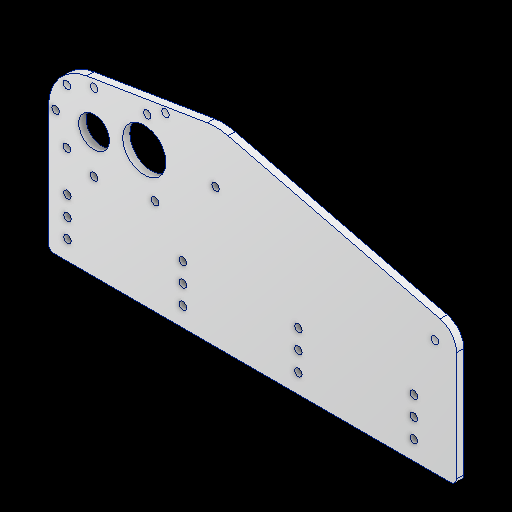
# Autodesk Inventor part: INTK_003_bar holder thingy
Saved by Autodesk Inventor 2027.1 (Build 311270010, 270A)
## iProperties
Created: 2026-11-21
Part Number: INTK_003_bar holder thingy
Material: Aluminum 6061
Document SubType Name: Modeling
Designer: Stanley Ruangsuwan
Density: 2.7 g/cm^3
Appearance: Aluminum - Flat
Author: Stanley Ruangsuwan
Autodesk Inventor part; units mm, degrees
ref_plane "YZ Plane" through (0, 0, 0) normal (1, 0, 0) x (0, 1, 0)
ref_plane "XZ Plane" through (0, 0, 0) normal (0, 1, 0) x (-1, 0, 0)
ref_plane "XY Plane" through (0, 0, 0) normal (0, 0, 1) x (1, 0, 0)
sketch "Sketch1" plane through (0, 0, 0) normal (0, 0, 1) x (1, 0, 0)
  circle A0 centre (-159.0509, 91.44) radius 34.29
  circle A1 centre (-14.2875, 76.2) radius 14.2875
  circle A2 centre (-159.0509, 91.44) radius 2.4892
  circle A3 centre (-14.2875, 76.2) radius 2.4892
  line L0 (-150.8089, 124.7247) -> (-10.8533, 90.0686)
  line L1 (0, 76.2) -> (0, 50.8)
  line L2 (-269.5173, 50.8) -> (0, 50.8)
  line L3 (0, 50.8) -> (-269.5173, 50.8)
  line L4 (-269.5173, 50.8) -> (-269.5173, 0)
  line L5 (-269.5173, 0) -> (0, 0)
  line L6 (0, 0) -> (0, 50.8)
  circle A4 centre (-256.8173, 38.1) radius 2.4892
  circle A5 centre (-256.8173, 25.4) radius 2.4892
  circle A6 centre (-256.8173, 12.7) radius 2.4892
  circle A7 centre (-180.6173, 38.1) radius 2.4892
  circle A8 centre (-180.6173, 25.4) radius 2.4892
  circle A9 centre (-180.6173, 12.7) radius 2.4892
  circle A10 centre (-104.4173, 38.1) radius 2.4892
  circle A11 centre (-104.4173, 25.4) radius 2.4892
  circle A12 centre (-104.4173, 12.7) radius 2.4892
  circle A13 centre (-28.2173, 38.1) radius 2.4892
  circle A14 centre (-28.2173, 25.4) radius 2.4892
  circle A15 centre (-28.2173, 12.7) radius 2.4892
  circle A16 centre (-239.2133, 82.6403) radius 30.0609
  circle A17 centre (-239.2133, 108.0403) radius 2.4892
  circle A18 centre (-206.1171, 88.9) radius 12.7 construction
  circle A19 centre (-239.2133, 82.6403) radius 10.16
  circle A20 centre (-257.1738, 100.6008) radius 2.4892
  circle A21 centre (-264.6133, 82.6403) radius 2.4892
  circle A22 centre (-257.1738, 64.6798) radius 2.4892
  circle A23 centre (-206.1171, 88.9) radius 14.2875
  line L7 (-164.5749, 125.2821) -> (-244.056, 112.3085)
  line L8 (-269.2734, 82.869) -> (-269.5173, 50.8)
  circle A24 centre (-204.1552, 110.3165) radius 6.35 construction
  line L9 (-209.1393, 106.3819) -> (-215.6186, 101.2668)
  line L10 (-198.2975, 107.865) -> (-190.6825, 104.6781)
  circle A25 centre (-198.9862, 63.2284) radius 6.35 construction
  line L11 (-204.7052, 65.9881) -> (-212.1398, 69.5757)
  line L12 (-193.7998, 66.8922) -> (-187.0575, 71.6552)
  circle A26 centre (-204.1552, 110.3165) radius 2.4892
  circle A27 centre (-198.9862, 63.2284) radius 2.4892
  circle A28 centre (-239.2133, 57.2403) radius 2.4892
  circle A29 centre (-192.0809, 117.0349) radius 6.35 construction
  circle A30 centre (-192.0809, 117.0349) radius 2.4892
  dimension "d0" = 68.58
  dimension "d1" = 28.575
  dimension "d5" = 4.9784
  dimension "d7" = 50.8
  dimension "d8" = 12.7
  dimension "d11" = 12.7
  dimension "d14" = 76.2
  dimension "d17" = 139.9556
  dimension "d19" = 25.4
  dimension "d20" = 12.7
  dimension "d21" = 40.64
  dimension "d22" = 4.9784
  dimension "d25" = 60.1218
  dimension "d27" = 25.4
  dimension "d32" = 47.0662
  dimension "d33" = 25.4
  dimension "d34" = 269.5174
  dimension "d35" = 20.32
  dimension "d38" = 180
  dimension "d40" = 28.575
  dimension "d41" = 33.0962
  dimension "d42" = 31.8403
  dimension "d43" = 38.1
  dimension "d44" = 12.7
  dimension "d45" = 8.255
  dimension "d56" = 80.1624
  dimension "d57" = 80.6439
  dimension "d59" = 33.683
  dimension "d60" = 12.7
  dimension "d61" = 13.8176
  dimension "d62" = 3.7084
  dimension "d63" = 4.9784
  constraints: 31 centre point, 26 end point, 14 point on circle, 9 coincident, 8 point on line, 6 tangent, 5 equal radius, 3 equal length, 3 horizontal, 2 parallel, 2 vertical, 1 perpendicular, 1 vertical alignment, 31 other
  measures "d0" diameter of A0
  measures "d1" diameter of A1
  measures "d5" diameter of A2
  measures "d7" distance of L3.end L4.end
  measures "d8" distance from line of L2 A4.centre
  measures "d11" distance of A4.centre A5.centre
  measures "d14" distance of A4.centre A7.centre
  measures "d17" horizontal distance of L0.start L0.end
  measures "d19" distance of L1.start L1.end
  measures "d20" distance from line of L4 A4.centre
  measures "d21" distance from line of L3 A0.centre
  measures "d22" diameter of A4
  measures "d25" diameter of A16
  measures "d27" distance of A16.centre A17.centre
  measures "d32" horizontal distance of A0.centre A18.centre
  measures "d33" diameter of A18
  measures "d34" distance between parallel lines of L6 L4
  measures "d35" diameter of A19
  measures "d40" diameter of A23
  measures "d41" horizontal distance of A23.centre A16.centre
  measures "d42" distance from line of L2 A16.centre
  measures "d43" distance from line of L2 A23.centre
  measures "d44" diameter of A24
  measures "d45" distance of L9.start L9.end
  measures "d56" horizontal distance of A0.centre A16.centre
  measures "d57" distance of A19.centre A2.centre
  measures "d59" distance of A23.centre A19.centre
  measures "d60" diameter of A29
  measures "d61" distance of A24.centre A29.centre
  measures "d62" distance from line of L7 A29.centre
  measures "d63" diameter of A30
extrude "Extrusion1" add sketch "Sketch1" along normal blind 4.7625 contours A0 A23 | A0 L0 A1 L1 L2 L8 A16 A23 | A0 A23 A16 L7 | A1 | A16 A23 | L6 L5 L4 L2 picked at (-181.9076, 95.5133) picked at (-230.7621, 63.8421)
fillet "Fillet1" radius 4 2 edges at (0, 0, 2.3813) (-269.5173, 0, 2.3813)
body "Solid1"
